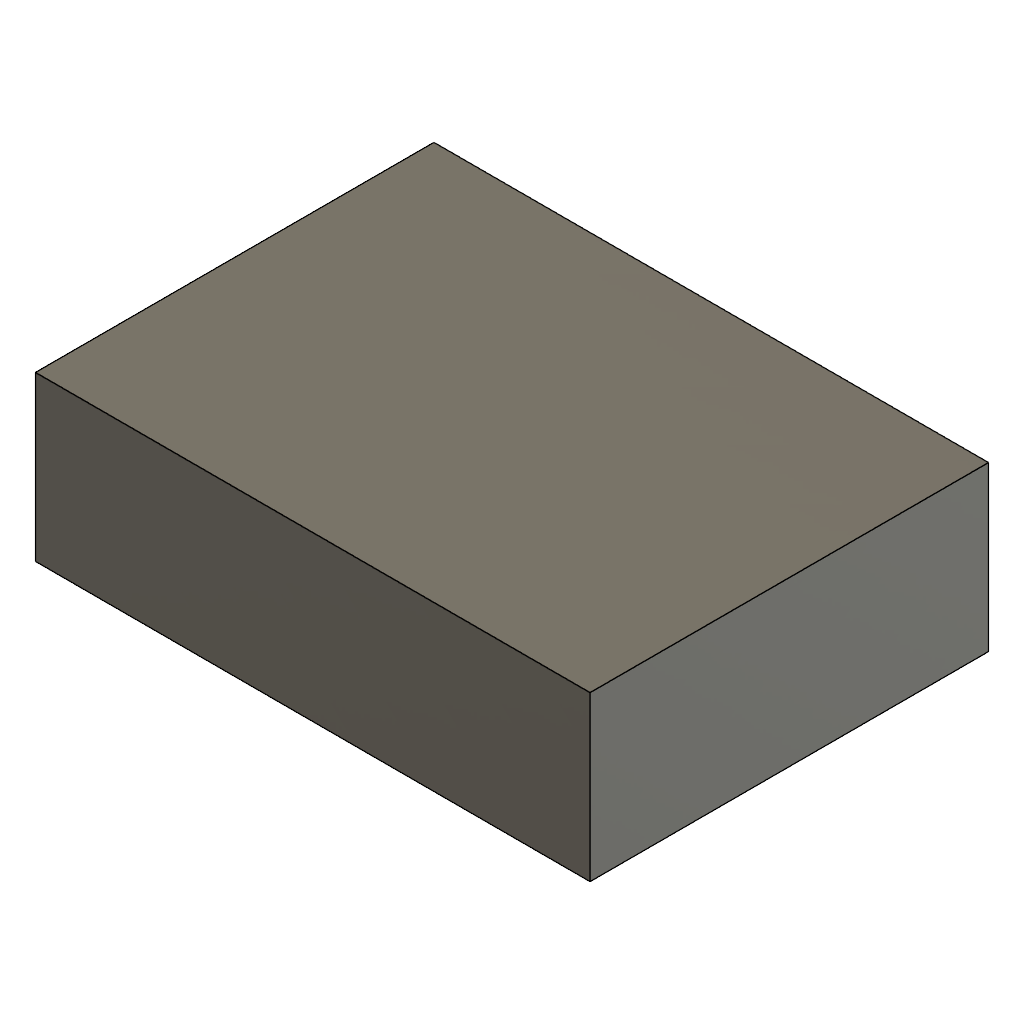
HoldoutControl (Autodesk Fusion 360 design; units mm, degrees)
part number: 2026-11-25-21-17-16-425
Autodesk Fusion 360 part; units mm, degrees
sketch "Encoder Rectangle" plane through (0, 0, 0) normal (0, 0, 1) x (1, 0, 0)
  line L0 (0, 0) -> (43.7, 0)
  line L1 (43.7, 0) -> (43.7, 12.9)
  line L2 (43.7, 12.9) -> (0, 12.9)
  line L3 (0, 12.9) -> (0, 0)
  dimension "d4" = 43.7
  dimension "d5" = 12.9
  constraint horizontal L0
  constraint vertical L1
  constraint horizontal L2
  constraint vertical L3
  measures "d4" horizontal distance of L0.start L0.end
  measures "d5" vertical distance of L0.start L2.end
extrude "Encoder Extrusion" add sketch "Encoder Rectangle" along normal blind 31.4
equation "kitWidth = 43.7 mm"
equation "kitDepth = 12.9 mm"
equation "kitHeight = 31.4 mm"
equation "d4 = kitWidth"
equation "d5 = kitDepth"
equation "d6 = kitHeight"
named bodies: "Encoder Cuboid"
